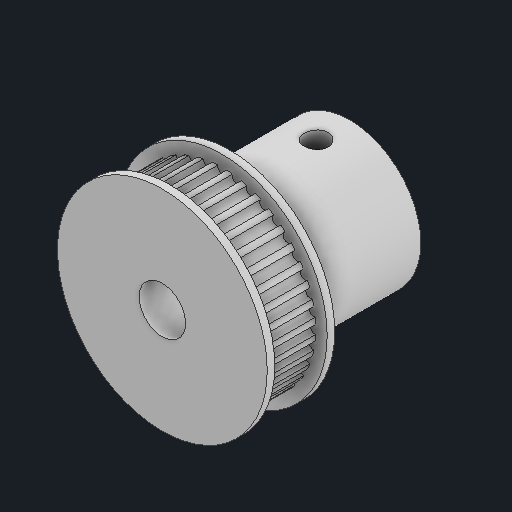
# Autodesk Inventor part: ra_worm_pulley_40T_printed
Saved by Autodesk Inventor 2027.1 (Build 311270010, 270A)
## iProperties
Created: 2026-11-11
Part Number: ra_worm_pulley_40T_printed
Material: Generic
Description: RA worm pulley GT2 40T, PRINTED, long hub: grips the 9 mm brass stub (6.2 bore, M3 grub + nut) through the frame U-slot; teeth z 53.5..60.5 (2026-11-11)
Document SubType Name: Modeling
Designer: alexg
Density: 1 g/cm^3
Appearance: Default
Author: alexg
Autodesk Inventor part; units mm, degrees
ref_plane "Work Plane1" through (0, 0, 36.5) normal (0, 0, 1) x (1, 0, 0)
sketch3d "Hub 19 dia (through the frame U-slot r11) z 36.5..52.5 sketc"
  constraints: 1 centre point
sketch "Hub 19 dia (through the frame U-slot r11) z 36.5..52.5 sketch" plane through (0, 0, 36.5) normal (0, 0, 1) x (1, 0, 0)
  circle A0 centre (62, -42) radius 9.5
extrude "Hub 19 dia (through the frame U-slot r11) z 36.5..52.5" add sketch "Hub 19 dia (through the frame U-slot r11) z 36.5..52.5 sketch" along normal blind 16
ref_plane "Work Plane2" through (0, 0, 52.5) normal (0, 0, 1) x (1, 0, 0)
sketch "Inner flange 28 sketch" plane through (0, 0, 52.5) normal (0, 0, 1) x (1, 0, 0)
  circle A0 centre (62, -42) radius 14
  constraints: 1 centre point
extrude "Inner flange 28" add sketch "Inner flange 28 sketch" along normal blind 1
ref_plane "Work Plane3" through (0, 0, 53.5) normal (0, 0, 1) x (1, 0, 0)
sketch "Tooth body 24.96 (GT2 40T OD) sketch" plane through (0, 0, 53.5) normal (0, 0, 1) x (1, 0, 0)
  circle A0 centre (62, -42) radius 12.48
  constraints: 1 centre point
extrude "Tooth body 24.96 (GT2 40T OD)" add sketch "Tooth body 24.96 (GT2 40T OD) sketch" along normal blind 7
ref_plane "Work Plane4" through (0, 0, 60.5) normal (0, 0, 1) x (1, 0, 0)
sketch "Outer flange 28 sketch" plane through (0, 0, 60.5) normal (0, 0, 1) x (1, 0, 0)
  circle A0 centre (62, -42) radius 14
  constraints: 1 centre point
extrude "Outer flange 28" add sketch "Outer flange 28 sketch" along normal blind 1
ref_plane "Work Plane5" through (0, 0, 53.5) normal (0, 0, 1) x (1, 0, 0)
sketch "GT2 tooth gaps x40 (0.75 deep, 1.16 wide) sketch" plane through (0, 0, 53.5) normal (0, 0, 1) x (1, 0, 0)
  circle A0 centre (74.33, -42) radius 0.6
  circle A1 centre (74.1782, -40.0712) radius 0.6
  circle A2 centre (73.7265, -38.1898) radius 0.6
  circle A3 centre (72.9861, -36.4023) radius 0.6
  circle A4 centre (71.9752, -34.7526) radius 0.6
  circle A5 centre (70.7186, -33.2814) radius 0.6
  circle A6 centre (69.2474, -32.0248) radius 0.6
  circle A7 centre (67.5977, -31.0139) radius 0.6
  circle A8 centre (65.8102, -30.2735) radius 0.6
  circle A9 centre (63.9288, -29.8218) radius 0.6
  circle A10 centre (62, -29.67) radius 0.6
  circle A11 centre (60.0712, -29.8218) radius 0.6
  circle A12 centre (58.1898, -30.2735) radius 0.6
  circle A13 centre (56.4023, -31.0139) radius 0.6
  circle A14 centre (54.7526, -32.0248) radius 0.6
  circle A15 centre (53.2814, -33.2814) radius 0.6
  circle A16 centre (52.0248, -34.7526) radius 0.6
  circle A17 centre (51.0139, -36.4023) radius 0.6
  circle A18 centre (50.2735, -38.1898) radius 0.6
  circle A19 centre (49.8218, -40.0712) radius 0.6
  circle A20 centre (49.67, -42) radius 0.6
  circle A21 centre (49.8218, -43.9288) radius 0.6
  circle A22 centre (50.2735, -45.8102) radius 0.6
  circle A23 centre (51.0139, -47.5977) radius 0.6
  circle A24 centre (52.0248, -49.2474) radius 0.6
  circle A25 centre (53.2814, -50.7186) radius 0.6
  circle A26 centre (54.7526, -51.9752) radius 0.6
  circle A27 centre (56.4023, -52.9861) radius 0.6
  circle A28 centre (58.1898, -53.7265) radius 0.6
  circle A29 centre (60.0712, -54.1782) radius 0.6
  circle A30 centre (62, -54.33) radius 0.6
  circle A31 centre (63.9288, -54.1782) radius 0.6
  circle A32 centre (65.8102, -53.7265) radius 0.6
  circle A33 centre (67.5977, -52.9861) radius 0.6
  circle A34 centre (69.2474, -51.9752) radius 0.6
  circle A35 centre (70.7186, -50.7186) radius 0.6
  circle A36 centre (71.9752, -49.2474) radius 0.6
  circle A37 centre (72.9861, -47.5977) radius 0.6
  circle A38 centre (73.7265, -45.8102) radius 0.6
  circle A39 centre (74.1782, -43.9288) radius 0.6
  constraints: 40 centre point
extrude "GT2 tooth gaps x40 (0.75 deep, 1.16 wide)" cut sketch "GT2 tooth gaps x40 (0.75 deep, 1.16 wide) sketch" along normal blind 7
ref_plane "Work Plane6" through (0, 0, 36.5) normal (0, 0, 1) x (1, 0, 0)
sketch "Bore 6.2 (6 mm brass stub, 9 mm engaged) sketch" plane through (0, 0, 36.5) normal (0, 0, 1) x (1, 0, 0)
  circle A0 centre (62, -42) radius 3.1
  constraints: 1 centre point
extrude "Bore 6.2 (6 mm brass stub, 9 mm engaged)" cut sketch "Bore 6.2 (6 mm brass stub, 9 mm engaged) sketch" along normal blind 25
ref_plane "Work Plane7" through (0, -32.5, 0) normal (0, 1, 0) x (-1, 0, 0)
sketch "M3 grub hole (top, over the stub at z 41) sketch" plane through (0, -32.5, 0) normal (0, 1, 0) x (-1, 0, 0)
  circle A0 centre (-62, 41) radius 1.6
  constraints: 1 centre point
extrude "M3 grub hole (top, over the stub at z 41)" cut sketch "M3 grub hole (top, over the stub at z 41) sketch" against normal blind 9.5
ref_plane "Work Plane8" through (0, 0, 36.5) normal (0, 0, 1) x (1, 0, 0)
sketch "M3 nut slot (slides in from the inboard end) sketch" plane through (0, 0, 36.5) normal (0, 0, 1) x (1, 0, 0)
  line L0 (59.15, -38) -> (64.85, -38)
  line L1 (64.85, -38) -> (64.85, -35.4)
  line L2 (64.85, -35.4) -> (59.15, -35.4)
  line L3 (59.15, -35.4) -> (59.15, -38)
  constraints: 8 end point, 2 parallel, 1 horizontal, 1 perpendicular
extrude "M3 nut slot (slides in from the inboard end)" cut sketch "M3 nut slot (slides in from the inboard end) sketch" along normal blind 7.7
body "Solid1"
